Autodesk Fusion 360 part; units mm, degrees
(part 12 of 28)
  line L3712 (128.2348, 62.9256) -> (128.0411, 62.9563)
  line L3713 (128.0411, 62.9563) -> (127.8545, 63.0169)
  line L3714 (127.8545, 63.0169) -> (127.6798, 63.106)
  line L3715 (127.6798, 63.106) -> (127.5211, 63.2213)
  line L3716 (127.5211, 63.2213) -> (127.3824, 63.36)
  line L3717 (127.3824, 63.36) -> (127.2671, 63.5186)
  line L3718 (127.2671, 63.5186) -> (127.178, 63.6934)
  line L3719 (127.178, 63.6934) -> (127.1174, 63.88)
  line L3720 (127.1174, 63.88) -> (127.0867, 64.0737)
  line L3721 (127.0867, 64.0737) -> (127.0867, 64.2698)
  line L3722 (127.0867, 64.2698) -> (127.1174, 64.4636)
  line L3723 (127.1174, 64.4636) -> (127.178, 64.6501)
  line L3724 (127.178, 64.6501) -> (127.2671, 64.8249)
  line L3725 (127.2671, 64.8249) -> (127.3824, 64.9836)
  line L3726 (127.3824, 64.9836) -> (127.5211, 65.1223)
  line L3727 (127.5211, 65.1223) -> (127.6798, 65.2376)
  line L3728 (127.6798, 65.2376) -> (127.8545, 65.3266)
  line L3729 (127.8545, 65.3266) -> (128.0411, 65.3872)
  line L3730 (128.0411, 65.3872) -> (128.2348, 65.4179)
  line L3731 (128.2348, 65.4179) -> (128.3329, 65.4218)
  line L3732 (128.3329, 65.4218) -> (128.8329, 65.4218)
  line L3733 (128.8329, 65.4218) -> (128.931, 65.4179)
  line L3734 (33.8595, 93.523) -> (34.046, 93.4624)
  line L3735 (34.046, 93.4624) -> (34.2208, 93.3733)
  line L3736 (34.2208, 93.3733) -> (34.3795, 93.258)
  line L3737 (34.3795, 93.258) -> (34.5182, 93.1193)
  line L3738 (34.5182, 93.1193) -> (34.6335, 92.9607)
  line L3739 (34.6335, 92.9607) -> (34.7225, 92.7859)
  line L3740 (34.7225, 92.7859) -> (34.7832, 92.5993)
  line L3741 (34.7832, 92.5993) -> (34.8138, 92.4056)
  line L3742 (34.8138, 92.4056) -> (34.8177, 92.3075)
  line L3743 (34.8177, 92.3075) -> (34.8177, 91.8075)
  line L3744 (34.8177, 91.8075) -> (34.8138, 91.7095)
  line L3745 (34.8138, 91.7095) -> (34.8071, 91.6667)
  line L3746 (34.8071, 91.6667) -> (37.2538, 89.22)
  line L3747 (37.2538, 89.22) -> (37.3055, 89.161)
  line L3748 (37.3055, 89.161) -> (37.3838, 89.0253)
  line L3749 (37.3838, 89.0253) -> (37.4244, 88.8741)
  line L3750 (37.4244, 88.8741) -> (37.4295, 88.7957)
  line L3751 (37.4295, 88.7957) -> (37.4295, 72.8232)
  line L3752 (37.4295, 72.8232) -> (37.4244, 72.7449)
  line L3753 (37.4244, 72.7449) -> (37.3838, 72.5936)
  line L3754 (37.3838, 72.5936) -> (37.3055, 72.4579)
  line L3755 (37.3055, 72.4579) -> (37.2538, 72.3989)
  line L3756 (37.2538, 72.3989) -> (33.9574, 69.1026)
  line L3757 (33.9574, 69.1026) -> (33.9642, 69.0598)
  line L3758 (33.9642, 69.0598) -> (33.968, 68.9617)
  line L3759 (33.968, 68.9617) -> (33.968, 68.4617)
  line L3760 (33.968, 68.4617) -> (33.9642, 68.3637)
  line L3761 (33.9642, 68.3637) -> (33.9335, 68.1699)
  line L3762 (33.9335, 68.1699) -> (33.8729, 67.9834)
  line L3763 (33.8729, 67.9834) -> (33.7838, 67.8086)
  line L3764 (33.7838, 67.8086) -> (33.6686, 67.6499)
  line L3765 (33.6686, 67.6499) -> (33.5299, 67.5112)
  line L3766 (33.5299, 67.5112) -> (33.3712, 67.3959)
  line L3767 (33.3712, 67.3959) -> (33.1964, 67.3069)
  line L3768 (33.1964, 67.3069) -> (33.0098, 67.2463)
  line L3769 (33.0098, 67.2463) -> (32.8161, 67.2156)
  line L3770 (32.8161, 67.2156) -> (32.62, 67.2156)
  line L3771 (32.62, 67.2156) -> (32.4262, 67.2463)
  line L3772 (32.4262, 67.2463) -> (32.2397, 67.3069)
  line L3773 (32.2397, 67.3069) -> (32.0649, 67.3959)
  line L3774 (32.0649, 67.3959) -> (31.9062, 67.5112)
  line L3775 (31.9062, 67.5112) -> (31.7675, 67.6499)
  line L3776 (31.7675, 67.6499) -> (31.6522, 67.8086)
  line L3777 (31.6522, 67.8086) -> (31.5632, 67.9834)
  line L3778 (31.5632, 67.9834) -> (31.5026, 68.1699)
  line L3779 (31.5026, 68.1699) -> (31.4719, 68.3637)
  line L3780 (31.4719, 68.3637) -> (31.468, 68.4617)
  line L3781 (31.468, 68.4617) -> (31.468, 68.9617)
  line L3782 (31.468, 68.9617) -> (31.4719, 69.0598)
  line L3783 (31.4719, 69.0598) -> (31.5026, 69.2535)
  line L3784 (31.5026, 69.2535) -> (31.5632, 69.4401)
  line L3785 (31.5632, 69.4401) -> (31.6522, 69.6149)
  line L3786 (31.6522, 69.6149) -> (31.7675, 69.7736)
  line L3787 (31.7675, 69.7736) -> (31.9062, 69.9122)
  line L3788 (31.9062, 69.9122) -> (32.0649, 70.0275)
  line L3789 (32.0649, 70.0275) -> (32.2397, 70.1166)
  line L3790 (32.2397, 70.1166) -> (32.4262, 70.1772)
  line L3791 (32.4262, 70.1772) -> (32.62, 70.2079)
  line L3792 (32.62, 70.2079) -> (32.8161, 70.2079)
  line L3793 (32.8161, 70.2079) -> (33.0098, 70.1772)
  line L3794 (33.0098, 70.1772) -> (33.1964, 70.1166)
  line L3795 (33.1964, 70.1166) -> (33.248, 70.0903)
  line L3796 (33.248, 70.0903) -> (36.2295, 73.0717)
  line L3797 (36.2295, 73.0717) -> (36.2295, 88.5472)
  line L3798 (36.2295, 88.5472) -> (34.0977, 90.679)
  line L3799 (34.0977, 90.679) -> (34.046, 90.6527)
  line L3800 (34.046, 90.6527) -> (33.8595, 90.5921)
  line L3801 (33.8595, 90.5921) -> (33.6658, 90.5614)
  line L3802 (33.6658, 90.5614) -> (33.4696, 90.5614)
  line L3803 (33.4696, 90.5614) -> (33.2759, 90.5921)
  line L3804 (33.2759, 90.5921) -> (33.0893, 90.6527)
  line L3805 (33.0893, 90.6527) -> (32.9146, 90.7417)
  line L3806 (32.9146, 90.7417) -> (32.7559, 90.857)
  line L3807 (32.7559, 90.857) -> (32.6172, 90.9957)
  line L3808 (32.6172, 90.9957) -> (32.5019, 91.1544)
  line L3809 (32.5019, 91.1544) -> (32.4128, 91.3292)
  line L3810 (32.4128, 91.3292) -> (32.3974, 91.3767)
  line L3811 (32.3974, 91.3767) -> (23.1427, 82.122)
  line L3812 (23.1427, 82.122) -> (23.169, 82.0704)
  line L3813 (23.169, 82.0704) -> (23.2296, 81.8838)
  line L3814 (23.2296, 81.8838) -> (23.2603, 81.6901)
  line L3815 (23.2603, 81.6901) -> (23.2603, 81.494)
  line L3816 (23.2603, 81.494) -> (23.2296, 81.3002)
  line L3817 (23.2296, 81.3002) -> (23.169, 81.1137)
  line L3818 (23.169, 81.1137) -> (23.08, 80.9389)
  line L3819 (23.08, 80.9389) -> (22.9647, 80.7802)
  line L3820 (22.9647, 80.7802) -> (22.826, 80.6415)
  line L3821 (22.826, 80.6415) -> (22.6673, 80.5262)
  line L3822 (22.6673, 80.5262) -> (22.4925, 80.4372)
  line L3823 (22.4925, 80.4372) -> (22.306, 80.3766)
  line L3824 (22.306, 80.3766) -> (22.1123, 80.3459)
  line L3825 (22.1123, 80.3459) -> (22.0142, 80.342)
  line L3826 (22.0142, 80.342) -> (21.5142, 80.342)
  line L3827 (21.5142, 80.342) -> (21.4161, 80.3459)
  line L3828 (21.4161, 80.3459) -> (21.2224, 80.3766)
  line L3829 (21.2224, 80.3766) -> (21.0358, 80.4372)
  line L3830 (21.0358, 80.4372) -> (20.8611, 80.5262)
  line L3831 (20.8611, 80.5262) -> (20.7024, 80.6415)
  line L3832 (20.7024, 80.6415) -> (20.5637, 80.7802)
  line L3833 (20.5637, 80.7802) -> (20.4484, 80.9389)
  line L3834 (20.4484, 80.9389) -> (20.3593, 81.1137)
  line L3835 (20.3593, 81.1137) -> (20.2987, 81.3002)
  line L3836 (20.2987, 81.3002) -> (20.268, 81.494)
  line L3837 (20.268, 81.494) -> (20.268, 81.6901)
  line L3838 (20.268, 81.6901) -> (20.2987, 81.8838)
  line L3839 (20.2987, 81.8838) -> (20.3593, 82.0704)
  line L3840 (20.3593, 82.0704) -> (20.4484, 82.2452)
  line L3841 (20.4484, 82.2452) -> (20.5637, 82.4038)
  line L3842 (20.5637, 82.4038) -> (20.7024, 82.5425)
  line L3843 (20.7024, 82.5425) -> (20.8611, 82.6578)
  line L3844 (20.8611, 82.6578) -> (21.0358, 82.7469)
  line L3845 (21.0358, 82.7469) -> (21.2224, 82.8075)
  line L3846 (21.2224, 82.8075) -> (21.4161, 82.8382)
  line L3847 (21.4161, 82.8382) -> (21.5142, 82.842)
  line L3848 (21.5142, 82.842) -> (22.0142, 82.842)
  line L3849 (22.0142, 82.842) -> (22.1123, 82.8382)
  line L3850 (22.1123, 82.8382) -> (22.155, 82.8314)
  line L3851 (22.155, 82.8314) -> (31.8054, 92.4818)
  line L3852 (31.8054, 92.4818) -> (31.8644, 92.5335)
  line L3853 (31.8644, 92.5335) -> (32.0001, 92.6119)
  line L3854 (32.0001, 92.6119) -> (32.1514, 92.6524)
  line L3855 (32.1514, 92.6524) -> (32.2297, 92.6575)
  line L3856 (32.2297, 92.6575) -> (32.3711, 92.6575)
  line L3857 (32.3711, 92.6575) -> (32.4128, 92.7859)
  line L3858 (32.4128, 92.7859) -> (32.5019, 92.9607)
  line L3859 (32.5019, 92.9607) -> (32.6172, 93.1193)
  line L3860 (32.6172, 93.1193) -> (32.7559, 93.258)
  line L3861 (32.7559, 93.258) -> (32.9146, 93.3733)
  line L3862 (32.9146, 93.3733) -> (33.0893, 93.4624)
  line L3863 (33.0893, 93.4624) -> (33.2759, 93.523)
  line L3864 (33.2759, 93.523) -> (33.4696, 93.5537)
  line L3865 (33.4696, 93.5537) -> (33.6658, 93.5537)
  line L3866 (33.6658, 93.5537) -> (33.8595, 93.523)
  line L3867 (68.7845, 93.523) -> (68.971, 93.4624)
  line L3868 (68.971, 93.4624) -> (69.1458, 93.3733)
  line L3869 (69.1458, 93.3733) -> (69.3045, 93.258)
  line L3870 (69.3045, 93.258) -> (69.4432, 93.1193)
  line L3871 (69.4432, 93.1193) -> (69.5585, 92.9607)
  line L3872 (69.5585, 92.9607) -> (69.6475, 92.7859)
  line L3873 (69.6475, 92.7859) -> (69.7082, 92.5993)
  line L3874 (69.7082, 92.5993) -> (69.7388, 92.4056)
  line L3875 (69.7388, 92.4056) -> (69.7427, 92.3075)
  line L3876 (69.7427, 92.3075) -> (69.7427, 91.8075)
  line L3877 (69.7427, 91.8075) -> (69.7388, 91.7095)
  line L3878 (69.7388, 91.7095) -> (69.7321, 91.6667)
  line L3879 (69.7321, 91.6667) -> (72.1788, 89.22)
  line L3880 (72.1788, 89.22) -> (72.2305, 89.161)
  line L3881 (72.2305, 89.161) -> (72.3088, 89.0253)
  line L3882 (72.3088, 89.0253) -> (72.3494, 88.8741)
  line L3883 (72.3494, 88.8741) -> (72.3545, 88.7957)
  line L3884 (72.3545, 88.7957) -> (72.3545, 72.8232)
  line L3885 (72.3545, 72.8232) -> (72.3494, 72.7449)
  line L3886 (72.3494, 72.7449) -> (72.3088, 72.5936)
  line L3887 (72.3088, 72.5936) -> (72.2305, 72.4579)
  line L3888 (72.2305, 72.4579) -> (72.1788, 72.3989)
  line L3889 (72.1788, 72.3989) -> (68.8824, 69.1026)
  line L3890 (68.8824, 69.1026) -> (68.8892, 69.0598)
  line L3891 (68.8892, 69.0598) -> (68.893, 68.9617)
  line L3892 (68.893, 68.9617) -> (68.893, 68.4617)
  line L3893 (68.893, 68.4617) -> (68.8892, 68.3637)
  line L3894 (68.8892, 68.3637) -> (68.8585, 68.1699)
  line L3895 (68.8585, 68.1699) -> (68.7979, 67.9834)
  line L3896 (68.7979, 67.9834) -> (68.7088, 67.8086)
  line L3897 (68.7088, 67.8086) -> (68.5935, 67.6499)
  line L3898 (68.5935, 67.6499) -> (68.4549, 67.5112)
  line L3899 (68.4549, 67.5112) -> (68.2962, 67.3959)
  line L3900 (68.2962, 67.3959) -> (68.1214, 67.3069)
  line L3901 (68.1214, 67.3069) -> (67.9348, 67.2463)
  line L3902 (67.9348, 67.2463) -> (67.7411, 67.2156)
  line L3903 (67.7411, 67.2156) -> (67.545, 67.2156)
  line L3904 (67.545, 67.2156) -> (67.3512, 67.2463)
  line L3905 (67.3512, 67.2463) -> (67.1647, 67.3069)
  line L3906 (67.1647, 67.3069) -> (66.9899, 67.3959)
  line L3907 (66.9899, 67.3959) -> (66.8312, 67.5112)
  line L3908 (66.8312, 67.5112) -> (66.6925, 67.6499)
  line L3909 (66.6925, 67.6499) -> (66.5772, 67.8086)
  line L3910 (66.5772, 67.8086) -> (66.4882, 67.9834)
  line L3911 (66.4882, 67.9834) -> (66.4276, 68.1699)
  line L3912 (66.4276, 68.1699) -> (66.3969, 68.3637)
  line L3913 (66.3969, 68.3637) -> (66.393, 68.4617)
  line L3914 (66.393, 68.4617) -> (66.393, 68.9617)
  line L3915 (66.393, 68.9617) -> (66.3969, 69.0598)
  line L3916 (66.3969, 69.0598) -> (66.4276, 69.2535)
  line L3917 (66.4276, 69.2535) -> (66.4882, 69.4401)
  line L3918 (66.4882, 69.4401) -> (66.5772, 69.6149)
  line L3919 (66.5772, 69.6149) -> (66.6925, 69.7736)
  line L3920 (66.6925, 69.7736) -> (66.8312, 69.9122)
  line L3921 (66.8312, 69.9122) -> (66.9899, 70.0275)
  line L3922 (66.9899, 70.0275) -> (67.1647, 70.1166)
  line L3923 (67.1647, 70.1166) -> (67.3512, 70.1772)
  line L3924 (67.3512, 70.1772) -> (67.545, 70.2079)
  line L3925 (67.545, 70.2079) -> (67.7411, 70.2079)
  line L3926 (67.7411, 70.2079) -> (67.9348, 70.1772)
  line L3927 (67.9349, 70.1772) -> (68.1214, 70.1166)
  line L3928 (68.1214, 70.1166) -> (68.173, 70.0903)
  line L3929 (68.173, 70.0903) -> (71.1545, 73.0717)
  line L3930 (71.1545, 73.0717) -> (71.1545, 88.5472)
  line L3931 (71.1545, 88.5472) -> (69.0227, 90.679)
  line L3932 (69.0227, 90.679) -> (68.971, 90.6527)
  line L3933 (68.971, 90.6527) -> (68.7845, 90.5921)
  line L3934 (68.7845, 90.5921) -> (68.5908, 90.5614)
  line L3935 (68.5908, 90.5614) -> (68.3946, 90.5614)
  line L3936 (68.3946, 90.5614) -> (68.2009, 90.5921)
  line L3937 (68.2009, 90.5921) -> (68.0143, 90.6527)
  line L3938 (68.0143, 90.6527) -> (67.8396, 90.7417)
  line L3939 (67.8396, 90.7417) -> (67.6809, 90.857)
  line L3940 (67.6809, 90.857) -> (67.5422, 90.9957)
  line L3941 (67.5422, 90.9957) -> (67.4269, 91.1544)
  line L3942 (67.4269, 91.1544) -> (67.3378, 91.3292)
  line L3943 (67.3378, 91.3292) -> (67.3224, 91.3767)
  line L3944 (67.3224, 91.3767) -> (58.0677, 82.122)
  line L3945 (58.0677, 82.122) -> (58.094, 82.0704)
  line L3946 (58.094, 82.0704) -> (58.1546, 81.8838)
  line L3947 (58.1546, 81.8838) -> (58.1853, 81.6901)
  line L3948 (58.1853, 81.6901) -> (58.1853, 81.494)
  line L3949 (58.1853, 81.494) -> (58.1546, 81.3002)
  line L3950 (58.1546, 81.3002) -> (58.094, 81.1137)
  line L3951 (58.094, 81.1137) -> (58.005, 80.9389)
  line L3952 (58.005, 80.9389) -> (57.8897, 80.7802)
  line L3953 (57.8897, 80.7802) -> (57.751, 80.6415)
  line L3954 (57.751, 80.6415) -> (57.5923, 80.5262)
  line L3955 (57.5923, 80.5262) -> (57.4175, 80.4372)
  line L3956 (57.4175, 80.4372) -> (57.231, 80.3766)
  line L3957 (57.231, 80.3766) -> (57.0373, 80.3459)
  line L3958 (57.0373, 80.3459) -> (56.9392, 80.342)
  line L3959 (56.9392, 80.342) -> (56.4392, 80.342)
  line L3960 (56.4392, 80.342) -> (56.3411, 80.3459)
  line L3961 (56.3411, 80.3459) -> (56.1474, 80.3766)
  line L3962 (56.1474, 80.3766) -> (55.9608, 80.4372)
  line L3963 (55.9608, 80.4372) -> (55.7861, 80.5262)
  line L3964 (55.7861, 80.5262) -> (55.6274, 80.6415)
  line L3965 (55.6274, 80.6415) -> (55.4887, 80.7802)
  line L3966 (55.4887, 80.7802) -> (55.3734, 80.9389)
  line L3967 (55.3734, 80.9389) -> (55.2843, 81.1137)
  line L3968 (55.2843, 81.1137) -> (55.2237, 81.3002)
  line L3969 (55.2237, 81.3002) -> (55.193, 81.494)
  line L3970 (55.193, 81.494) -> (55.193, 81.6901)
  line L3971 (55.193, 81.6901) -> (55.2237, 81.8838)
  line L3972 (55.2237, 81.8838) -> (55.2843, 82.0704)
  line L3973 (55.2843, 82.0704) -> (55.3734, 82.2452)
  line L3974 (55.3734, 82.2452) -> (55.4887, 82.4038)
  line L3975 (55.4887, 82.4038) -> (55.6274, 82.5425)
  line L3976 (55.6274, 82.5425) -> (55.7861, 82.6578)
  line L3977 (55.7861, 82.6578) -> (55.9608, 82.7469)
  line L3978 (55.9608, 82.7469) -> (56.1474, 82.8075)
  line L3979 (56.1474, 82.8075) -> (56.3411, 82.8382)
  line L3980 (56.3411, 82.8382) -> (56.4392, 82.842)
  line L3981 (56.4392, 82.842) -> (56.9392, 82.842)
  line L3982 (56.9392, 82.842) -> (57.0373, 82.8382)
  line L3983 (57.0373, 82.8382) -> (57.08, 82.8314)
  line L3984 (57.08, 82.8314) -> (66.7304, 92.4818)
  line L3985 (66.7304, 92.4818) -> (66.7894, 92.5335)
  line L3986 (66.7894, 92.5335) -> (66.9251, 92.6119)
  line L3987 (66.9251, 92.6119) -> (67.0764, 92.6524)
  line L3988 (67.0764, 92.6524) -> (67.1547, 92.6575)
  line L3989 (67.1547, 92.6575) -> (67.2961, 92.6575)
  line L3990 (67.2961, 92.6575) -> (67.3378, 92.7859)
  line L3991 (67.3378, 92.7859) -> (67.4269, 92.9607)
  line L3992 (67.4269, 92.9607) -> (67.5422, 93.1193)
  line L3993 (67.5422, 93.1193) -> (67.6809, 93.258)
  line L3994 (67.6809, 93.258) -> (67.8396, 93.3733)
  line L3995 (67.8396, 93.3733) -> (68.0143, 93.4624)
  line L3996 (68.0143, 93.4624) -> (68.2009, 93.523)
  line L3997 (68.2009, 93.523) -> (68.3946, 93.5537)
  line L3998 (68.3946, 93.5537) -> (68.5908, 93.5537)
  line L3999 (68.5908, 93.5537) -> (68.7845, 93.523)
  line L4000 (103.7095, 93.523) -> (103.896, 93.4624)
  line L4001 (103.896, 93.4624) -> (104.0708, 93.3733)
  line L4002 (104.0708, 93.3733) -> (104.2295, 93.258)
  line L4003 (104.2295, 93.258) -> (104.3682, 93.1193)
  line L4004 (104.3682, 93.1193) -> (104.4835, 92.9607)
  line L4005 (104.4835, 92.9607) -> (104.5725, 92.7859)
  line L4006 (104.5725, 92.7859) -> (104.6332, 92.5993)
  line L4007 (104.6332, 92.5993) -> (104.6638, 92.4056)
  line L4008 (104.6638, 92.4056) -> (104.6677, 92.3075)
  line L4009 (104.6677, 92.3075) -> (104.6677, 91.8075)
  line L4010 (104.6677, 91.8075) -> (104.6638, 91.7095)
  line L4011 (104.6638, 91.7095) -> (104.6571, 91.6667)
  line L4012 (104.6571, 91.6667) -> (107.1038, 89.22)
  line L4013 (107.1038, 89.22) -> (107.1555, 89.161)
  line L4014 (107.1555, 89.161) -> (107.2338, 89.0253)
  line L4015 (107.2338, 89.0253) -> (107.2744, 88.8741)
  line L4016 (107.2744, 88.8741) -> (107.2795, 88.7957)
  line L4017 (107.2795, 88.7957) -> (107.2795, 72.8232)
  line L4018 (107.2795, 72.8232) -> (107.2744, 72.7449)
  line L4019 (107.2744, 72.7449) -> (107.2338, 72.5936)
  line L4020 (107.2338, 72.5936) -> (107.1555, 72.4579)
  line L4021 (107.1555, 72.4579) -> (107.1038, 72.3989)
  line L4022 (107.1038, 72.3989) -> (103.8074, 69.1026)
  line L4023 (103.8074, 69.1026) -> (103.8142, 69.0598)
  line L4024 (103.8142, 69.0598) -> (103.818, 68.9617)
  line L4025 (103.818, 68.9617) -> (103.818, 68.4617)
  line L4026 (103.818, 68.4617) -> (103.8142, 68.3637)
  line L4027 (103.8142, 68.3637) -> (103.7835, 68.1699)
  line L4028 (103.7835, 68.1699) -> (103.7229, 67.9834)
  line L4029 (103.7229, 67.9834) -> (103.6338, 67.8086)
  line L4030 (103.6338, 67.8086) -> (103.5186, 67.6499)
  line L4031 (103.5186, 67.6499) -> (103.3799, 67.5112)
  line L4032 (103.3799, 67.5112) -> (103.2212, 67.3959)
  line L4033 (103.2212, 67.3959) -> (103.0464, 67.3069)
  line L4034 (103.0464, 67.3069) -> (102.8598, 67.2463)
  line L4035 (102.8598, 67.2463) -> (102.6661, 67.2156)
  line L4036 (102.6661, 67.2156) -> (102.47, 67.2156)
  line L4037 (102.47, 67.2156) -> (102.2762, 67.2463)
  line L4038 (102.2762, 67.2463) -> (102.0897, 67.3069)
  line L4039 (102.0897, 67.3069) -> (101.9149, 67.3959)
  line L4040 (101.9149, 67.3959) -> (101.7562, 67.5112)
  line L4041 (101.7562, 67.5112) -> (101.6175, 67.6499)
  line L4042 (101.6175, 67.6499) -> (101.5022, 67.8086)
  line L4043 (101.5022, 67.8086) -> (101.4132, 67.9834)
  line L4044 (101.4132, 67.9834) -> (101.3526, 68.1699)
  line L4045 (101.3526, 68.1699) -> (101.3219, 68.3637)
  line L4046 (101.3219, 68.3637) -> (101.318, 68.4617)
  line L4047 (101.318, 68.4617) -> (101.318, 68.9617)
  line L4048 (101.318, 68.9617) -> (101.3219, 69.0598)
  line L4049 (101.3219, 69.0598) -> (101.3526, 69.2535)
  line L4050 (101.3526, 69.2535) -> (101.4132, 69.4401)
  line L4051 (101.4132, 69.4401) -> (101.5022, 69.6149)
  line L4052 (101.5022, 69.6149) -> (101.6175, 69.7736)
  line L4053 (101.6175, 69.7736) -> (101.7562, 69.9122)
  line L4054 (101.7562, 69.9122) -> (101.9149, 70.0275)
  line L4055 (101.9149, 70.0275) -> (102.0897, 70.1166)
  line L4056 (102.0897, 70.1166) -> (102.2762, 70.1772)
  line L4057 (102.2762, 70.1772) -> (102.47, 70.2079)
  line L4058 (102.47, 70.2079) -> (102.6661, 70.2079)
  line L4059 (102.6661, 70.2079) -> (102.8598, 70.1772)
  line L4060 (102.8598, 70.1772) -> (103.0464, 70.1166)
  line L4061 (103.0464, 70.1166) -> (103.098, 70.0903)
  line L4062 (103.098, 70.0903) -> (106.0795, 73.0717)
  line L4063 (106.0795, 73.0717) -> (106.0795, 88.5472)
  line L4064 (106.0795, 88.5472) -> (103.9477, 90.679)
  line L4065 (103.9477, 90.679) -> (103.896, 90.6527)
  line L4066 (103.896, 90.6527) -> (103.7095, 90.5921)
  line L4067 (103.7095, 90.5921) -> (103.5158, 90.5614)
  line L4068 (103.5158, 90.5614) -> (103.3196, 90.5614)
  line L4069 (103.3196, 90.5614) -> (103.1259, 90.5921)
  line L4070 (103.1259, 90.5921) -> (102.9393, 90.6527)
  line L4071 (102.9393, 90.6527) -> (102.7646, 90.7417)
  line L4072 (102.7646, 90.7417) -> (102.6059, 90.857)
  line L4073 (102.6059, 90.857) -> (102.4672, 90.9957)
  line L4074 (102.4672, 90.9957) -> (102.3519, 91.1544)
  line L4075 (102.3519, 91.1544) -> (102.2628, 91.3292)
  line L4076 (102.2628, 91.3292) -> (102.2474, 91.3767)
  line L4077 (102.2474, 91.3767) -> (92.9927, 82.122)
  line L4078 (92.9927, 82.122) -> (93.019, 82.0704)
  line L4079 (93.019, 82.0704) -> (93.0796, 81.8838)
  line L4080 (93.0796, 81.8838) -> (93.1103, 81.6901)
  line L4081 (93.1103, 81.6901) -> (93.1103, 81.494)
  line L4082 (93.1103, 81.494) -> (93.0796, 81.3002)
  line L4083 (93.0796, 81.3002) -> (93.019, 81.1137)
  line L4084 (93.019, 81.1137) -> (92.93, 80.9389)
  line L4085 (92.93, 80.9389) -> (92.8147, 80.7802)
  line L4086 (92.8147, 80.7802) -> (92.676, 80.6415)
  line L4087 (92.676, 80.6415) -> (92.5173, 80.5262)
  line L4088 (92.5173, 80.5262) -> (92.3425, 80.4372)
  line L4089 (92.3425, 80.4372) -> (92.156, 80.3766)
  line L4090 (92.156, 80.3766) -> (91.9623, 80.3459)
  line L4091 (91.9623, 80.3459) -> (91.8642, 80.342)
  line L4092 (91.8642, 80.342) -> (91.3642, 80.342)
  line L4093 (91.3642, 80.342) -> (91.2661, 80.3459)
  line L4094 (91.2661, 80.3459) -> (91.0724, 80.3766)
  line L4095 (91.0724, 80.3766) -> (90.8858, 80.4372)
  line L4096 (90.8858, 80.4372) -> (90.7111, 80.5262)
  line L4097 (90.7111, 80.5262) -> (90.5524, 80.6415)
  line L4098 (90.5524, 80.6415) -> (90.4137, 80.7802)
  line L4099 (90.4137, 80.7802) -> (90.2984, 80.9389)
  line L4100 (90.2984, 80.9389) -> (90.2093, 81.1137)
  line L4101 (90.2093, 81.1137) -> (90.1487, 81.3002)
  line L4102 (90.1487, 81.3002) -> (90.118, 81.494)
  line L4103 (90.118, 81.494) -> (90.118, 81.6901)
  line L4104 (90.118, 81.6901) -> (90.1487, 81.8838)
  line L4105 (90.1487, 81.8838) -> (90.2093, 82.0704)
  line L4106 (90.2093, 82.0704) -> (90.2984, 82.2452)
  line L4107 (90.2984, 82.2452) -> (90.4137, 82.4038)
  line L4108 (90.4137, 82.4038) -> (90.5524, 82.5425)
  line L4109 (90.5524, 82.5425) -> (90.7111, 82.6578)
  line L4110 (90.7111, 82.6578) -> (90.8858, 82.7469)
  line L4111 (90.8858, 82.7469) -> (91.0724, 82.8075)
  line L4112 (91.0724, 82.8075) -> (91.2661, 82.8382)
  line L4113 (91.2661, 82.8382) -> (91.3642, 82.842)
  line L4114 (91.3642, 82.842) -> (91.8642, 82.842)
  line L4115 (91.8642, 82.842) -> (91.9623, 82.8382)
  line L4116 (91.9623, 82.8382) -> (92.005, 82.8314)
  line L4117 (92.005, 82.8314) -> (101.6554, 92.4818)
  line L4118 (101.6554, 92.4818) -> (101.7144, 92.5335)
  line L4119 (101.7144, 92.5335) -> (101.8501, 92.6119)
  line L4120 (101.8501, 92.6119) -> (102.0014, 92.6524)
  line L4121 (102.0014, 92.6524) -> (102.0797, 92.6575)
  line L4122 (102.0797, 92.6575) -> (102.2211, 92.6575)
  line L4123 (102.2211, 92.6575) -> (102.2628, 92.7859)
  line L4124 (102.2628, 92.7859) -> (102.3519, 92.9607)
  line L4125 (102.3519, 92.9607) -> (102.4672, 93.1193)
  line L4126 (102.4672, 93.1193) -> (102.6059, 93.258)
  line L4127 (102.6059, 93.258) -> (102.7646, 93.3733)
  line L4128 (102.7646, 93.3733) -> (102.9393, 93.4624)
  line L4129 (102.9393, 93.4624) -> (103.1259, 93.523)
  line L4130 (103.1259, 93.523) -> (103.3196, 93.5537)
  line L4131 (103.3196, 93.5537) -> (103.5158, 93.5537)
  line L4132 (103.5158, 93.5537) -> (103.7095, 93.523)
  line L4133 (138.6345, 93.523) -> (138.821, 93.4624)
  line L4134 (138.821, 93.4624) -> (138.9958, 93.3733)
  line L4135 (138.9958, 93.3733) -> (139.1545, 93.258)
  line L4136 (139.1545, 93.258) -> (139.2932, 93.1193)
  line L4137 (139.2932, 93.1193) -> (139.4085, 92.9607)
  line L4138 (139.4085, 92.9607) -> (139.4975, 92.7859)
  line L4139 (139.4975, 92.7859) -> (139.5582, 92.5993)
  line L4140 (139.5582, 92.5993) -> (139.5888, 92.4056)
  line L4141 (139.5888, 92.4056) -> (139.5927, 92.3075)
  line L4142 (139.5927, 92.3075) -> (139.5927, 91.8075)
  line L4143 (139.5927, 91.8075) -> (139.5888, 91.7095)
  line L4144 (139.5888, 91.7095) -> (139.5821, 91.6667)
  line L4145 (139.5821, 91.6667) -> (142.0288, 89.22)
  line L4146 (142.0288, 89.22) -> (142.0805, 89.161)
  line L4147 (142.0805, 89.161) -> (142.1588, 89.0253)
  line L4148 (142.1588, 89.0253) -> (142.1994, 88.8741)
  line L4149 (142.1994, 88.8741) -> (142.2045, 88.7957)
  line L4150 (142.2045, 88.7957) -> (142.2045, 72.8232)
  line L4151 (142.2045, 72.8232) -> (142.1994, 72.7449)
  line L4152 (142.1994, 72.7449) -> (142.1588, 72.5936)
  line L4153 (142.1588, 72.5936) -> (142.0805, 72.4579)
  line L4154 (142.0805, 72.4579) -> (142.0288, 72.3989)
  line L4155 (142.0288, 72.3989) -> (138.7324, 69.1026)
  line L4156 (138.7324, 69.1026) -> (138.7392, 69.0598)
  line L4157 (138.7392, 69.0598) -> (138.743, 68.9617)
  line L4158 (138.743, 68.9617) -> (138.743, 68.4617)
  line L4159 (138.743, 68.4617) -> (138.7392, 68.3637)
  line L4160 (138.7392, 68.3637) -> (138.7085, 68.1699)
  line L4161 (138.7085, 68.1699) -> (138.6479, 67.9834)
  line L4162 (138.6479, 67.9834) -> (138.5588, 67.8086)
  line L4163 (138.5588, 67.8086) -> (138.4436, 67.6499)
  line L4164 (138.4436, 67.6499) -> (138.3049, 67.5112)
  line L4165 (138.3049, 67.5112) -> (138.1462, 67.3959)
  line L4166 (138.1462, 67.3959) -> (137.9714, 67.3069)
  line L4167 (137.9714, 67.3069) -> (137.7849, 67.2463)
  line L4168 (137.7849, 67.2463) -> (137.5911, 67.2156)
  line L4169 (137.5911, 67.2156) -> (137.395, 67.2156)
  line L4170 (137.395, 67.2156) -> (137.2012, 67.2463)
  line L4171 (137.2012, 67.2463) -> (137.0147, 67.3069)
  line L4172 (137.0147, 67.3069) -> (136.8399, 67.3959)
  line L4173 (136.8399, 67.3959) -> (136.6812, 67.5112)
  line L4174 (136.6812, 67.5112) -> (136.5425, 67.6499)
  line L4175 (136.5425, 67.6499) -> (136.4272, 67.8086)
  line L4176 (136.4272, 67.8086) -> (136.3382, 67.9834)
  line L4177 (136.3382, 67.9834) -> (136.2776, 68.1699)
  line L4178 (136.2776, 68.1699) -> (136.2469, 68.3637)
  line L4179 (136.2469, 68.3637) -> (136.243, 68.4617)
  line L4180 (136.243, 68.4617) -> (136.243, 68.9617)
  line L4181 (136.243, 68.9617) -> (136.2469, 69.0598)
  line L4182 (136.2469, 69.0598) -> (136.2776, 69.2535)
  line L4183 (136.2776, 69.2535) -> (136.3382, 69.4401)
  line L4184 (136.3382, 69.4401) -> (136.4272, 69.6149)
  line L4185 (136.4272, 69.6149) -> (136.5425, 69.7736)
  line L4186 (136.5425, 69.7736) -> (136.6812, 69.9122)
  line L4187 (136.6812, 69.9122) -> (136.8399, 70.0275)
  line L4188 (136.8399, 70.0275) -> (137.0147, 70.1166)
  line L4189 (137.0147, 70.1166) -> (137.2012, 70.1772)
  line L4190 (137.2012, 70.1772) -> (137.395, 70.2079)
  line L4191 (137.395, 70.2079) -> (137.5911, 70.2079)
  line L4192 (137.5911, 70.2079) -> (137.7849, 70.1772)
  line L4193 (137.7849, 70.1772) -> (137.9714, 70.1166)
  line L4194 (137.9714, 70.1166) -> (138.023, 70.0903)
  line L4195 (138.023, 70.0903) -> (141.0045, 73.0717)
  line L4196 (141.0045, 73.0717) -> (141.0045, 88.5472)
  line L4197 (141.0045, 88.5472) -> (138.8727, 90.679)
  line L4198 (138.8727, 90.679) -> (138.821, 90.6527)
  line L4199 (138.821, 90.6527) -> (138.6345, 90.5921)
  line L4200 (138.6345, 90.5921) -> (138.4408, 90.5614)
  line L4201 (138.4408, 90.5614) -> (138.2446, 90.5614)
  line L4202 (138.2446, 90.5614) -> (138.0509, 90.5921)
  line L4203 (138.0509, 90.5921) -> (137.8643, 90.6527)
  line L4204 (137.8643, 90.6527) -> (137.6896, 90.7417)
  line L4205 (137.6896, 90.7417) -> (137.5309, 90.857)
  line L4206 (137.5309, 90.857) -> (137.3922, 90.9957)
  line L4207 (137.3922, 90.9957) -> (137.2769, 91.1544)
  line L4208 (137.2769, 91.1544) -> (137.1878, 91.3292)
  line L4209 (137.1878, 91.3292) -> (137.1724, 91.3767)
  line L4210 (137.1724, 91.3767) -> (127.9177, 82.122)
  line L4211 (127.9177, 82.122) -> (127.944, 82.0704)
  line L4212 (127.944, 82.0704) -> (128.0046, 81.8838)
  line L4213 (128.0046, 81.8838) -> (128.0353, 81.6901)
  line L4214 (128.0353, 81.6901) -> (128.0353, 81.494)
  line L4215 (128.0353, 81.494) -> (128.0046, 81.3002)
  line L4216 (128.0046, 81.3002) -> (127.944, 81.1137)
  line L4217 (127.944, 81.1137) -> (127.855, 80.9389)
  line L4218 (127.855, 80.9389) -> (127.7397, 80.7802)
  line L4219 (127.7397, 80.7802) -> (127.601, 80.6415)
  line L4220 (127.601, 80.6415) -> (127.4423, 80.5262)
  line L4221 (127.4423, 80.5262) -> (127.2675, 80.4372)
  line L4222 (127.2675, 80.4372) -> (127.081, 80.3766)
  line L4223 (127.081, 80.3766) -> (126.8873, 80.3459)
  line L4224 (126.8873, 80.3459) -> (126.7892, 80.342)
  line L4225 (126.7892, 80.342) -> (126.2892, 80.342)
  line L4226 (126.2892, 80.342) -> (126.1911, 80.3459)
  line L4227 (126.1911, 80.3459) -> (125.9974, 80.3766)
  line L4228 (125.9974, 80.3766) -> (125.8108, 80.4372)
  line L4229 (125.8108, 80.4372) -> (125.6361, 80.5262)
  line L4230 (125.6361, 80.5262) -> (125.4774, 80.6415)
  line L4231 (125.4774, 80.6415) -> (125.3387, 80.7802)
  line L4232 (125.3387, 80.7802) -> (125.2234, 80.9389)
  line L4233 (125.2234, 80.9389) -> (125.1343, 81.1137)
  line L4234 (125.1343, 81.1137) -> (125.0737, 81.3002)
  line L4235 (125.0737, 81.3002) -> (125.043, 81.494)
  line L4236 (125.043, 81.494) -> (125.043, 81.6901)
  line L4237 (125.043, 81.6901) -> (125.0737, 81.8838)
  line L4238 (125.0737, 81.8838) -> (125.1343, 82.0704)
  line L4239 (125.1343, 82.0704) -> (125.2234, 82.2452)
  line L4240 (125.2234, 82.2452) -> (125.3387, 82.4038)
  line L4241 (125.3387, 82.4038) -> (125.4774, 82.5425)
  line L4242 (125.4774, 82.5425) -> (125.6361, 82.6578)
  line L4243 (125.6361, 82.6578) -> (125.8108, 82.7469)
  line L4244 (125.8108, 82.7469) -> (125.9974, 82.8075)
  line L4245 (125.9974, 82.8075) -> (126.1911, 82.8382)
  line L4246 (126.1911, 82.8382) -> (126.2892, 82.842)
  line L4247 (126.2892, 82.842) -> (126.7892, 82.842)
  line L4248 (126.7892, 82.842) -> (126.8873, 82.8382)
  line L4249 (126.8873, 82.8382) -> (126.93, 82.8314)
  line L4250 (126.93, 82.8314) -> (136.5804, 92.4818)
  line L4251 (136.5804, 92.4818) -> (136.6394, 92.5335)
  line L4252 (136.6394, 92.5335) -> (136.7751, 92.6119)
  line L4253 (136.7751, 92.6119) -> (136.9264, 92.6524)
  line L4254 (136.9264, 92.6524) -> (137.0047, 92.6575)
  line L4255 (137.0047, 92.6575) -> (137.1461, 92.6575)
  line L4256 (137.1461, 92.6575) -> (137.1878, 92.7859)
  line L4257 (137.1878, 92.7859) -> (137.2769, 92.9607)
  line L4258 (137.2769, 92.9607) -> (137.3922, 93.1193)
  line L4259 (137.3922, 93.1193) -> (137.5309, 93.258)
  line L4260 (137.5309, 93.258) -> (137.6896, 93.3733)
  line L4261 (137.6896, 93.3733) -> (137.8643, 93.4624)
  line L4262 (137.8643, 93.4624) -> (138.0509, 93.523)
  line L4263 (138.0509, 93.523) -> (138.2446, 93.5537)
  line L4264 (138.2446, 93.5537) -> (138.4408, 93.5537)
  line L4265 (138.4408, 93.5537) -> (138.6345, 93.523)
  line L4266 (24.9416, 73.2403) -> (22.9416, 73.2403)
  line L4267 (22.9416, 73.2403) -> (22.9416, 76.4403)
  line L4268 (22.9416, 76.4403) -> (24.9416, 76.4403)
  line L4269 (24.9416, 76.4403) -> (24.9416, 73.2403)
  line L4270 (59.8666, 73.2403) -> (57.8666, 73.2403)
  line L4271 (57.8666, 73.2403) -> (57.8666, 76.4403)
  line L4272 (57.8666, 76.4403) -> (59.8666, 76.4403)
  line L4273 (59.8666, 76.4403) -> (59.8666, 73.2403)
  line L4274 (94.7916, 73.2403) -> (92.7916, 73.2403)
  line L4275 (92.7916, 73.2403) -> (92.7916, 76.4403)
  line L4276 (92.7916, 76.4403) -> (94.7916, 76.4403)
  line L4277 (94.7916, 76.4403) -> (94.7916, 73.2403)
  line L4278 (129.7166, 73.2403) -> (127.7166, 73.2403)
  line L4279 (127.7166, 73.2403) -> (127.7166, 76.4403)
  line L4280 (127.7166, 76.4403) -> (129.7166, 76.4403)
  line L4281 (129.7166, 76.4403) -> (129.7166, 73.2403)
  line L4282 (14.4065, 73.2985) -> (12.4065, 73.2985)
  line L4283 (12.4065, 73.2985) -> (12.4065, 76.4985)
  line L4284 (12.4065, 76.4985) -> (14.4065, 76.4985)
  line L4285 (14.4065, 76.4985) -> (14.4065, 73.2985)
  line L4286 (49.3315, 73.2985) -> (47.3315, 73.2985)
  line L4287 (47.3315, 73.2985) -> (47.3315, 76.4985)
  line L4288 (47.3315, 76.4985) -> (49.3315, 76.4985)
  line L4289 (49.3315, 76.4985) -> (49.3315, 73.2985)
  line L4290 (84.2565, 73.2985) -> (82.2565, 73.2985)
  line L4291 (82.2565, 73.2985) -> (82.2565, 76.4985)
  line L4292 (82.2565, 76.4985) -> (84.2565, 76.4985)
  line L4293 (84.2565, 76.4985) -> (84.2565, 73.2985)
  line L4294 (119.1815, 73.2985) -> (117.1815, 73.2985)
  line L4295 (117.1815, 73.2985) -> (117.1815, 76.4985)
  line L4296 (117.1815, 76.4985) -> (119.1815, 76.4985)
  line L4297 (119.1815, 76.4985) -> (119.1815, 73.2985)
  line L4298 (16.4668, 76.4554) -> (16.6479, 76.3804)
  line L4299 (16.6479, 76.3804) -> (16.8109, 76.2715)
  line L4300 (16.8109, 76.2715) -> (16.9495, 76.1329)
  line L4301 (16.9495, 76.1329) -> (17.0584, 75.9699)
  line L4302 (17.0584, 75.9699) -> (17.1335, 75.7888)
  line L4303 (17.1335, 75.7888) -> (17.1717, 75.5965)
  line L4304 (17.1717, 75.5965) -> (17.1765, 75.4985)
  line L4305 (17.1765, 75.4985) -> (17.1765, 74.2985)
  line L4306 (17.1765, 74.2985) -> (17.1717, 74.2005)
  line L4307 (17.1717, 74.2005) -> (17.1335, 74.0082)
  line L4308 (17.1335, 74.0082) -> (17.0584, 73.8271)
  line L4309 (17.0584, 73.8271) -> (16.9495, 73.6641)
  line L4310 (16.9495, 73.6641) -> (16.8109, 73.5255)
  line L4311 (16.8109, 73.5255) -> (16.6479, 73.4166)
  line L4312 (16.6479, 73.4166) -> (16.4668, 73.3415)
  line L4313 (16.4668, 73.3415) -> (16.2745, 73.3033)
  line L4314 (16.2745, 73.3033) -> (16.0785, 73.3033)
  line L4315 (16.0785, 73.3033) -> (15.8862, 73.3415)
  line L4316 (15.8862, 73.3415) -> (15.7051, 73.4166)
  line L4317 (15.7051, 73.4166) -> (15.5421, 73.5255)
  line L4318 (15.5421, 73.5255) -> (15.4035, 73.6641)
  line L4319 (15.4035, 73.6641) -> (15.2946, 73.8271)
  line L4320 (15.2946, 73.8271) -> (15.2196, 74.0082)
  line L4321 (15.2196, 74.0082) -> (15.1813, 74.2005)
  line L4322 (15.1813, 74.2005) -> (15.1765, 74.2985)
  line L4323 (15.1765, 74.2985) -> (15.1765, 75.4985)
  line L4324 (15.1765, 75.4985) -> (15.1813, 75.5965)
  line L4325 (15.1813, 75.5965) -> (15.2196, 75.7888)
  line L4326 (15.2196, 75.7888) -> (15.2946, 75.9699)
  line L4327 (15.2946, 75.9699) -> (15.4035, 76.1329)
  line L4328 (15.4035, 76.1329) -> (15.5421, 76.2715)
  line L4329 (15.5421, 76.2715) -> (15.7051, 76.3804)
  line L4330 (15.7051, 76.3804) -> (15.8862, 76.4554)
  line L4331 (15.8862, 76.4554) -> (16.0785, 76.4937)
  line L4332 (16.0785, 76.4937) -> (16.2745, 76.4937)
  line L4333 (16.2745, 76.4937) -> (16.4668, 76.4554)
  line L4334 (51.3918, 76.4554) -> (51.5729, 76.3804)
  line L4335 (51.5729, 76.3804) -> (51.7359, 76.2715)
  line L4336 (51.7359, 76.2715) -> (51.8745, 76.1329)
  line L4337 (51.8745, 76.1329) -> (51.9834, 75.9699)
  line L4338 (51.9834, 75.9699) -> (52.0585, 75.7888)
  line L4339 (52.0585, 75.7888) -> (52.0967, 75.5965)
  line L4340 (52.0967, 75.5965) -> (52.1015, 75.4985)
  line L4341 (52.1015, 75.4985) -> (52.1015, 74.2985)
  line L4342 (52.1015, 74.2985) -> (52.0967, 74.2005)
  line L4343 (52.0967, 74.2005) -> (52.0585, 74.0082)
  line L4344 (52.0585, 74.0082) -> (51.9834, 73.8271)
  line L4345 (51.9834, 73.8271) -> (51.8745, 73.6641)
  line L4346 (51.8745, 73.6641) -> (51.7359, 73.5255)
  line L4347 (51.7359, 73.5255) -> (51.5729, 73.4166)
  line L4348 (51.5729, 73.4166) -> (51.3918, 73.3415)
  line L4349 (51.3918, 73.3415) -> (51.1995, 73.3033)
  line L4350 (51.1995, 73.3033) -> (51.0035, 73.3033)
  line L4351 (51.0035, 73.3033) -> (50.8112, 73.3415)
  line L4352 (50.8112, 73.3415) -> (50.6301, 73.4166)
  line L4353 (50.6301, 73.4166) -> (50.4671, 73.5255)
  line L4354 (50.4671, 73.5255) -> (50.3285, 73.6641)
  line L4355 (50.3285, 73.6641) -> (50.2196, 73.8271)
  line L4356 (50.2196, 73.8271) -> (50.1446, 74.0082)
  line L4357 (50.1446, 74.0082) -> (50.1063, 74.2005)
  line L4358 (50.1063, 74.2005) -> (50.1015, 74.2985)
  line L4359 (50.1015, 74.2985) -> (50.1015, 75.4985)
  line L4360 (50.1015, 75.4985) -> (50.1063, 75.5965)
  line L4361 (50.1063, 75.5965) -> (50.1446, 75.7888)
  line L4362 (50.1446, 75.7888) -> (50.2196, 75.9699)
  line L4363 (50.2196, 75.9699) -> (50.3285, 76.1329)
  line L4364 (50.3285, 76.1329) -> (50.4671, 76.2715)
  line L4365 (50.4671, 76.2715) -> (50.6301, 76.3804)
  line L4366 (50.6301, 76.3804) -> (50.8112, 76.4554)
  line L4367 (50.8112, 76.4554) -> (51.0035, 76.4937)
  line L4368 (51.0035, 76.4937) -> (51.1995, 76.4937)
  line L4369 (51.1995, 76.4937) -> (51.3918, 76.4554)
  line L4370 (86.3168, 76.4554) -> (86.4979, 76.3804)
  line L4371 (86.4979, 76.3804) -> (86.6609, 76.2715)
  line L4372 (86.6609, 76.2715) -> (86.7995, 76.1329)
  line L4373 (86.7995, 76.1329) -> (86.9084, 75.9699)
  line L4374 (86.9084, 75.9699) -> (86.9835, 75.7888)
  line L4375 (86.9835, 75.7888) -> (87.0217, 75.5965)
  line L4376 (87.0217, 75.5965) -> (87.0265, 75.4985)
  line L4377 (87.0265, 75.4985) -> (87.0265, 74.2985)
  line L4378 (87.0265, 74.2985) -> (87.0217, 74.2005)
  line L4379 (87.0217, 74.2005) -> (86.9835, 74.0082)
  line L4380 (86.9835, 74.0082) -> (86.9084, 73.8271)
  line L4381 (86.9084, 73.8271) -> (86.7995, 73.6641)
  line L4382 (86.7995, 73.6641) -> (86.6609, 73.5255)
  line L4383 (86.6609, 73.5255) -> (86.4979, 73.4166)
  line L4384 (86.4979, 73.4166) -> (86.3168, 73.3415)
  line L4385 (86.3168, 73.3415) -> (86.1245, 73.3033)
  line L4386 (86.1245, 73.3033) -> (85.9285, 73.3033)
  line L4387 (85.9285, 73.3033) -> (85.7362, 73.3415)
  line L4388 (85.7362, 73.3415) -> (85.5551, 73.4166)
  line L4389 (85.5551, 73.4166) -> (85.3921, 73.5255)
  line L4390 (85.3921, 73.5255) -> (85.2535, 73.6641)
  line L4391 (85.2535, 73.6641) -> (85.1446, 73.8271)
  line L4392 (85.1446, 73.8271) -> (85.0696, 74.0082)
  line L4393 (85.0696, 74.0082) -> (85.0313, 74.2005)
  line L4394 (85.0313, 74.2005) -> (85.0265, 74.2985)
  line L4395 (85.0265, 74.2985) -> (85.0265, 75.4985)
  line L4396 (85.0265, 75.4985) -> (85.0313, 75.5965)
  line L4397 (85.0313, 75.5965) -> (85.0696, 75.7888)
  line L4398 (85.0696, 75.7888) -> (85.1446, 75.9699)
  line L4399 (85.1446, 75.9699) -> (85.2535, 76.1329)
  line L4400 (85.2535, 76.1329) -> (85.3921, 76.2715)
  line L4401 (85.3921, 76.2715) -> (85.5551, 76.3804)
  line L4402 (85.5551, 76.3804) -> (85.7362, 76.4554)
  line L4403 (85.7362, 76.4554) -> (85.9285, 76.4937)
  line L4404 (85.9285, 76.4937) -> (86.1245, 76.4937)
  line L4405 (86.1245, 76.4937) -> (86.3168, 76.4554)
  line L4406 (121.2418, 76.4554) -> (121.4229, 76.3804)
  line L4407 (121.4229, 76.3804) -> (121.5859, 76.2715)
  line L4408 (121.5859, 76.2715) -> (121.7245, 76.1329)
  line L4409 (121.7245, 76.1329) -> (121.8334, 75.9699)
  line L4410 (121.8334, 75.9699) -> (121.9085, 75.7888)
  line L4411 (121.9085, 75.7888) -> (121.9467, 75.5965)
  line L4412 (121.9467, 75.5965) -> (121.9515, 75.4985)
  line L4413 (121.9515, 75.4985) -> (121.9515, 74.2985)
  line L4414 (121.9515, 74.2985) -> (121.9467, 74.2005)
  line L4415 (121.9467, 74.2005) -> (121.9085, 74.0082)
  line L4416 (121.9085, 74.0082) -> (121.8334, 73.8271)
  line L4417 (121.8334, 73.8271) -> (121.7245, 73.6641)
  line L4418 (121.7245, 73.6641) -> (121.5859, 73.5255)
  line L4419 (121.5859, 73.5255) -> (121.4229, 73.4166)
  line L4420 (121.4229, 73.4166) -> (121.2418, 73.3415)
  line L4421 (121.2418, 73.3415) -> (121.0495, 73.3033)
  line L4422 (121.0495, 73.3033) -> (120.8535, 73.3033)
  line L4423 (120.8535, 73.3033) -> (120.6612, 73.3415)
  line L4424 (120.6612, 73.3415) -> (120.4801, 73.4166)
  line L4425 (120.4801, 73.4166) -> (120.3171, 73.5255)
  line L4426 (120.3171, 73.5255) -> (120.1785, 73.6641)
  line L4427 (120.1785, 73.6641) -> (120.0696, 73.8271)
  line L4428 (120.0696, 73.8271) -> (119.9946, 74.0082)
  line L4429 (119.9946, 74.0082) -> (119.9563, 74.2005)
  line L4430 (119.9563, 74.2005) -> (119.9515, 74.2985)
  line L4431 (119.9515, 74.2985) -> (119.9515, 75.4985)
  line L4432 (119.9515, 75.4985) -> (119.9563, 75.5965)
  line L4433 (119.9563, 75.5965) -> (119.9946, 75.7888)
  line L4434 (119.9946, 75.7888) -> (120.0696, 75.9699)
  line L4435 (120.0696, 75.9699) -> (120.1785, 76.1329)
  line L4436 (120.1785, 76.1329) -> (120.3171, 76.2715)
  line L4437 (120.3171, 76.2715) -> (120.4801, 76.3804)
  line L4438 (120.4801, 76.3804) -> (120.6612, 76.4554)
  line L4439 (120.6612, 76.4554) -> (120.8535, 76.4937)
  line L4440 (120.8535, 76.4937) -> (121.0495, 76.4937)
  line L4441 (121.0495, 76.4937) -> (121.2418, 76.4554)
  line L4442 (21.2733, 92.0395) -> (21.4562, 91.9801)
  line L4443 (21.4562, 91.9801) -> (21.6274, 91.8928)
  line L4444 (21.6274, 91.8928) -> (21.7829, 91.7798)
  line L4445 (21.7829, 91.7798) -> (21.9189, 91.6439)
  line L4446 (21.9189, 91.6439) -> (22.0319, 91.4884)
  line L4447 (22.0319, 91.4884) -> (22.1191, 91.3171)
  line L4448 (22.1191, 91.3171) -> (22.1785, 91.1343)
  line L4449 (22.1785, 91.1343) -> (22.2086, 90.9444)
  line L4450 (22.2086, 90.9444) -> (22.2124, 90.8483)
  line L4451 (22.2124, 90.8483) -> (22.2124, 90.2983)
  line L4452 (22.2124, 90.2983) -> (22.2086, 90.2022)
  line L4453 (22.2086, 90.2022) -> (22.1785, 90.0123)
  line L4454 (22.1785, 90.0123) -> (22.1191, 89.8295)
  line L4455 (22.1191, 89.8295) -> (22.0319, 89.6583)
  line L4456 (22.0319, 89.6583) -> (21.9189, 89.5027)
  line L4457 (21.9189, 89.5027) -> (21.7829, 89.3668)
  line L4458 (21.7829, 89.3668) -> (21.6274, 89.2538)
  line L4459 (21.6274, 89.2538) -> (21.4562, 89.1666)
  line L4460 (21.4562, 89.1666) -> (21.2733, 89.1072)
  line L4461 (21.2733, 89.1072) -> (21.0835, 89.0771)
  line L4462 (21.0835, 89.0771) -> (20.8913, 89.0771)
  line L4463 (20.8913, 89.0771) -> (20.7014, 89.1072)
  line L4464 (20.7014, 89.1072) -> (20.5186, 89.1666)
  line L4465 (20.5186, 89.1666) -> (20.3473, 89.2538)
  line L4466 (20.3473, 89.2538) -> (20.1918, 89.3668)
  line L4467 (20.1918, 89.3668) -> (20.0559, 89.5027)
  line L4468 (20.0559, 89.5027) -> (19.9761, 89.6126)
  line L4469 (19.9761, 89.6126) -> (14.7442, 84.3807)
  line L4470 (14.7442, 84.3807) -> (14.7442, 82.7886)
  line L4471 (14.7442, 82.7886) -> (14.8725, 82.7469)
  line L4472 (14.8725, 82.7469) -> (15.0473, 82.6578)
  line L4473 (15.0473, 82.6578) -> (15.206, 82.5425)
  line L4474 (15.206, 82.5425) -> (15.3447, 82.4038)
  line L4475 (15.3447, 82.4038) -> (15.46, 82.2452)
  line L4476 (15.46, 82.2452) -> (15.549, 82.0704)
  line L4477 (15.549, 82.0704) -> (15.6096, 81.8838)
  line L4478 (15.6096, 81.8838) -> (15.6403, 81.6901)
  line L4479 (15.6403, 81.6901) -> (15.6403, 81.494)
  line L4480 (15.6403, 81.494) -> (15.6096, 81.3002)
  line L4481 (15.6096, 81.3002) -> (15.549, 81.1137)
  line L4482 (15.549, 81.1137) -> (15.46, 80.9389)
  line L4483 (15.46, 80.9389) -> (15.3447, 80.7802)
  line L4484 (15.3447, 80.7802) -> (15.206, 80.6415)
  line L4485 (15.206, 80.6415) -> (15.0473, 80.5262)
  line L4486 (15.0473, 80.5262) -> (14.8725, 80.4372)
  line L4487 (14.8725, 80.4372) -> (14.686, 80.3766)
  line L4488 (14.686, 80.3766) -> (14.4923, 80.3459)
  line L4489 (14.4923, 80.3459) -> (14.3942, 80.342)
  line L4490 (14.3942, 80.342) -> (13.8942, 80.342)
  line L4491 (13.8942, 80.342) -> (13.7961, 80.3459)
  line L4492 (13.7961, 80.3459) -> (13.6024, 80.3766)
  line L4493 (13.6024, 80.3766) -> (13.4158, 80.4372)
  line L4494 (13.4158, 80.4372) -> (13.2411, 80.5262)
  line L4495 (13.2411, 80.5262) -> (13.0824, 80.6415)
  line L4496 (13.0824, 80.6415) -> (12.9437, 80.7802)
  line L4497 (12.9437, 80.7802) -> (12.8284, 80.9389)
  line L4498 (12.8284, 80.9389) -> (12.7393, 81.1137)
  line L4499 (12.7393, 81.1137) -> (12.6787, 81.3002)
  line L4500 (12.6787, 81.3002) -> (12.648, 81.494)
  line L4501 (12.648, 81.494) -> (12.648, 81.6901)
  line L4502 (12.648, 81.6901) -> (12.6787, 81.8838)
  line L4503 (12.6787, 81.8838) -> (12.7393, 82.0704)
  line L4504 (12.7393, 82.0704) -> (12.8284, 82.2452)
  line L4505 (12.8284, 82.2452) -> (12.9437, 82.4038)
  line L4506 (12.9437, 82.4038) -> (13.0824, 82.5425)
  line L4507 (13.0824, 82.5425) -> (13.2411, 82.6578)
  line L4508 (13.2411, 82.6578) -> (13.4158, 82.7469)
  line L4509 (13.4158, 82.7469) -> (13.5442, 82.7886)
  line L4510 (13.5442, 82.7886) -> (13.5442, 84.6292)
  line L4511 (13.5442, 84.6292) -> (13.5493, 84.7075)
  line L4512 (13.5493, 84.7075) -> (13.5899, 84.8588)
  line L4513 (13.5899, 84.8588) -> (13.6682, 84.9944)
  line L4514 (13.6682, 84.9944) -> (13.7199, 85.0535)
  line L4515 (13.7199, 85.0535) -> (19.664, 90.9976)
  line L4516 (19.664, 90.9976) -> (19.7231, 91.0493)
  line L4517 (19.7231, 91.0493) -> (19.7888, 91.0873)
  line L4518 (19.7888, 91.0873) -> (19.7962, 91.1343)
  line L4519 (19.7962, 91.1343) -> (19.8556, 91.3171)
  line L4520 (19.8556, 91.3171) -> (19.9429, 91.4884)
  line L4521 (19.9429, 91.4884) -> (20.0559, 91.6439)
  line L4522 (20.0559, 91.6439) -> (20.1918, 91.7798)
  line L4523 (20.1918, 91.7798) -> (20.3473, 91.8928)
  line L4524 (20.3473, 91.8928) -> (20.5186, 91.9801)
  line L4525 (20.5186, 91.9801) -> (20.7014, 92.0395)
  line L4526 (20.7014, 92.0395) -> (20.8913, 92.0695)
  line L4527 (20.8913, 92.0695) -> (21.0835, 92.0695)
  line L4528 (21.0835, 92.0695) -> (21.2733, 92.0395)
  line L4529 (56.1983, 92.0395) -> (56.3812, 91.9801)
  line L4530 (56.3812, 91.9801) -> (56.5524, 91.8928)
  line L4531 (56.5524, 91.8928) -> (56.7079, 91.7798)
  line L4532 (56.7079, 91.7798) -> (56.8439, 91.6439)
  line L4533 (56.8439, 91.6439) -> (56.9569, 91.4884)
  line L4534 (56.9569, 91.4884) -> (57.0441, 91.3171)
  line L4535 (57.0441, 91.3171) -> (57.1035, 91.1343)
  line L4536 (57.1035, 91.1343) -> (57.1336, 90.9444)
  line L4537 (57.1336, 90.9444) -> (57.1374, 90.8483)
  line L4538 (57.1374, 90.8483) -> (57.1374, 90.2983)
  line L4539 (57.1374, 90.2983) -> (57.1336, 90.2022)
  line L4540 (57.1336, 90.2022) -> (57.1035, 90.0123)
  line L4541 (57.1035, 90.0123) -> (57.0441, 89.8295)
  line L4542 (57.0441, 89.8295) -> (56.9569, 89.6583)
  line L4543 (56.9569, 89.6583) -> (56.8439, 89.5027)
  line L4544 (56.8439, 89.5027) -> (56.7079, 89.3668)
  line L4545 (56.7079, 89.3668) -> (56.5524, 89.2538)
  line L4546 (56.5524, 89.2538) -> (56.3812, 89.1666)
  line L4547 (56.3812, 89.1666) -> (56.1983, 89.1072)
  line L4548 (56.1983, 89.1072) -> (56.0085, 89.0771)
  line L4549 (56.0085, 89.0771) -> (55.8163, 89.0771)
  line L4550 (55.8163, 89.0771) -> (55.6264, 89.1072)
  line L4551 (55.6264, 89.1072) -> (55.4436, 89.1666)
  line L4552 (55.4436, 89.1666) -> (55.2723, 89.2538)
  line L4553 (55.2723, 89.2538) -> (55.1168, 89.3668)
  line L4554 (55.1168, 89.3668) -> (54.9809, 89.5027)
  line L4555 (54.9809, 89.5027) -> (54.9011, 89.6126)
  line L4556 (54.9011, 89.6126) -> (49.6692, 84.3807)
  line L4557 (49.6692, 84.3807) -> (49.6692, 82.7886)
  line L4558 (49.6692, 82.7886) -> (49.7975, 82.7469)
  line L4559 (49.7975, 82.7469) -> (49.9723, 82.6578)
  line L4560 (49.9723, 82.6578) -> (50.131, 82.5425)
  line L4561 (50.131, 82.5425) -> (50.2697, 82.4038)
  line L4562 (50.2697, 82.4038) -> (50.385, 82.2452)
  line L4563 (50.385, 82.2452) -> (50.474, 82.0704)
  line L4564 (50.474, 82.0704) -> (50.5346, 81.8838)
  line L4565 (50.5346, 81.8838) -> (50.5653, 81.6901)
  line L4566 (50.5653, 81.6901) -> (50.5653, 81.494)
  line L4567 (50.5653, 81.494) -> (50.5346, 81.3002)
  line L4568 (50.5346, 81.3002) -> (50.474, 81.1137)
  line L4569 (50.474, 81.1137) -> (50.385, 80.9389)
  line L4570 (50.385, 80.9389) -> (50.2697, 80.7802)
  line L4571 (50.2697, 80.7802) -> (50.131, 80.6415)
  line L4572 (50.131, 80.6415) -> (49.9723, 80.5262)
  line L4573 (49.9723, 80.5262) -> (49.7975, 80.4372)
  line L4574 (49.7975, 80.4372) -> (49.611, 80.3766)
  line L4575 (49.611, 80.3766) -> (49.4173, 80.3459)
  line L4576 (49.4173, 80.3459) -> (49.3192, 80.342)
  line L4577 (49.3192, 80.342) -> (48.8192, 80.342)
  line L4578 (48.8192, 80.342) -> (48.7211, 80.3459)
  line L4579 (48.7211, 80.3459) -> (48.5274, 80.3766)
  line L4580 (48.5274, 80.3766) -> (48.3408, 80.4372)
  line L4581 (48.3408, 80.4372) -> (48.1661, 80.5262)
  line L4582 (48.1661, 80.5262) -> (48.0074, 80.6415)
  line L4583 (48.0074, 80.6415) -> (47.8687, 80.7802)
  line L4584 (47.8687, 80.7802) -> (47.7534, 80.9389)
  line L4585 (47.7534, 80.9389) -> (47.6643, 81.1137)
  line L4586 (47.6643, 81.1137) -> (47.6037, 81.3002)
  line L4587 (47.6037, 81.3002) -> (47.573, 81.494)
  line L4588 (47.573, 81.494) -> (47.573, 81.6901)
  line L4589 (47.573, 81.6901) -> (47.6037, 81.8838)
  line L4590 (47.6037, 81.8838) -> (47.6643, 82.0704)
  line L4591 (47.6643, 82.0704) -> (47.7534, 82.2452)
  line L4592 (47.7534, 82.2452) -> (47.8687, 82.4038)
  line L4593 (47.8687, 82.4038) -> (48.0074, 82.5425)
  line L4594 (48.0074, 82.5425) -> (48.1661, 82.6578)
  line L4595 (48.1661, 82.6578) -> (48.3408, 82.7469)
  line L4596 (48.3408, 82.7469) -> (48.4692, 82.7886)
  line L4597 (48.4692, 82.7886) -> (48.4692, 84.6292)
  line L4598 (48.4692, 84.6292) -> (48.4743, 84.7075)
  line L4599 (48.4743, 84.7075) -> (48.5149, 84.8588)
  line L4600 (48.5149, 84.8588) -> (48.5932, 84.9944)
  line L4601 (48.5932, 84.9944) -> (48.6449, 85.0535)
  line L4602 (48.6449, 85.0535) -> (54.589, 90.9976)
  line L4603 (54.589, 90.9976) -> (54.6481, 91.0493)
  line L4604 (54.6481, 91.0493) -> (54.7138, 91.0873)
  line L4605 (54.7138, 91.0873) -> (54.7212, 91.1343)
  line L4606 (54.7212, 91.1343) -> (54.7806, 91.3171)
  line L4607 (54.7806, 91.3171) -> (54.8679, 91.4884)
  line L4608 (54.8679, 91.4884) -> (54.9809, 91.6439)
  line L4609 (54.9809, 91.6439) -> (55.1168, 91.7798)
  line L4610 (55.1168, 91.7798) -> (55.2723, 91.8928)
  line L4611 (55.2723, 91.8928) -> (55.4436, 91.9801)
  line L4612 (55.4436, 91.9801) -> (55.6264, 92.0395)
  line L4613 (55.6264, 92.0395) -> (55.8163, 92.0695)
  line L4614 (55.8163, 92.0695) -> (56.0085, 92.0695)
  line L4615 (56.0085, 92.0695) -> (56.1983, 92.0395)
  line L4616 (91.1233, 92.0395) -> (91.3062, 91.9801)
  line L4617 (91.3062, 91.9801) -> (91.4774, 91.8928)
  line L4618 (91.4774, 91.8928) -> (91.6329, 91.7798)
  line L4619 (91.6329, 91.7798) -> (91.7689, 91.6439)
  line L4620 (91.7689, 91.6439) -> (91.8819, 91.4884)
  line L4621 (91.8819, 91.4884) -> (91.9691, 91.3171)
  line L4622 (91.9691, 91.3171) -> (92.0285, 91.1343)
  line L4623 (92.0285, 91.1343) -> (92.0586, 90.9444)
  line L4624 (92.0586, 90.9444) -> (92.0624, 90.8483)
  line L4625 (92.0624, 90.8483) -> (92.0624, 90.2983)
  line L4626 (92.0624, 90.2983) -> (92.0586, 90.2022)
  line L4627 (92.0586, 90.2022) -> (92.0285, 90.0123)
  line L4628 (92.0285, 90.0123) -> (91.9691, 89.8295)
  line L4629 (91.9691, 89.8295) -> (91.8819, 89.6583)
  line L4630 (91.8819, 89.6583) -> (91.7689, 89.5027)
  line L4631 (91.7689, 89.5027) -> (91.6329, 89.3668)